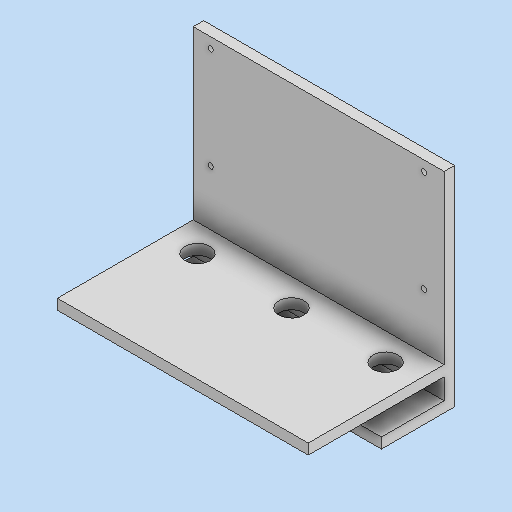
# Autodesk Inventor part: Support_arduino_grand_robot
Saved by Autodesk Inventor 2026 (Build 300175050, 175E)
## iProperties
Created: 2025-06-19
Part Number: Support_arduino_grand_robot
Material: Generisch
Document SubType Name: Modeling
Designer: karle
Density: 1 g/cm^3
Appearance: Vorgabe
Author: karle
Autodesk Inventor part; units mm, degrees
ref_plane "YZ Plane" through (0, 0, 0) normal (1, 0, 0) x (0, 1, 0)
ref_plane "XZ Plane" through (0, 0, 0) normal (0, 1, 0) x (-1, 0, 0)
ref_plane "XY Plane" through (0, 0, 0) normal (0, 0, 1) x (1, 0, 0)
sketch "Skizze1" plane through (0, 0, 0) normal (0, 0, 1) x (1, 0, 0)
  line L0 (-60, 0) -> (60, 0)
  line L1 (60, 0) -> (60, -100)
  line L2 (60, -100) -> (-60, -100)
  line L3 (-60, -100) -> (-60, 0)
  line L4 (0, 23.1579) -> (0, -78.4962)
  point P0 (0, 0)
  point P1 (0, 0)
  dimension "d0" = 120
  dimension "d1" = 100
  dimension "d2" = 0
  constraints: 10 end point, 2 parallel, 1 coincident, 1 horizontal, 1 midpoint, 1 perpendicular, 1 vertical, 1 other
  measures "d0" distance of L1.end L2.end
  measures "d1" distance between parallel lines of L2 L0
  measures "d2" distance from line of point (0, 0) L0
extrude "Extrusion1" add sketch "Skizze1" against normal blind 5
sketch "Skizze2" plane through (0, 0, 0) normal (0, 0, 1) x (1, 0, 0)
  line L0 (-60, -100) -> (-60, 0) projected
  line L1 (60, -100) -> (-60, -100) projected
  line L2 (-60, -95) -> (60, -95)
  line L3 (60, -95) -> (60, -100)
  line L4 (60, -100) -> (-60, -100)
  line L5 (-60, -100) -> (-60, -95)
  line L6 (-60, -80) -> (60, -80)
  line L7 (60, -80) -> (60, -85)
  line L8 (60, -85) -> (-60, -85)
  line L9 (-60, -85) -> (-60, -80)
  point P0 (0, 0)
  point P1 (-60, -85)
  dimension "d5" = 5
  dimension "d6" = 5
  dimension "d7" = 15
  constraints: 16 end point, 4 parallel, 3 point on line, 2 horizontal, 2 perpendicular
  measures "d5" distance between parallel lines of L1 L2
  measures "d6" distance between parallel lines of L8 L6
  measures "d7" distance between parallel lines of L1 L8
extrude "Extrusion2" add sketch "Skizze2" along normal blind 30 contours L0 L2 L3 L1
extrude "Extrusion3" add sketch "Skizze2" along normal blind 65 contours L0 L6 L7 L8
sketch "Skizze3" plane through (0, 0, 0) normal (0, 0, 1) x (1, 0, 0)
  line L0 (0, 0) -> (0, -100.1543)
  line L1 (60, 0) -> (-60, 0) projected
  point P0 (-51.627, -5)
  point P1 (50.373, -5)
  point P2 (50.373, -53.5)
  point P3 (-51.627, -53.5)
  dimension "d12" = 102
  dimension "d13" = 48.5
  dimension "d14" = 5
  constraints: 2 end point, 1 horizontal alignment, 1 vertical
  measures "d12" distance of point (50.373, -5) point (-51.627, -5)
  measures "d13" distance of point (50.373, -53.5) point (50.373, -5)
  measures "d14" distance from line of point (50.373, -5) L1
hole "Bohrung1" at (50.373, -5, 0) at (50.373, -53.5, 0) at (-51.627, -53.5, 0) at (-51.627, -5, 0) direction (0, 0, -1) diameter 2.5 end through all clearance for "Flachkopfmaschinenschraube" size "M2" standard "ANSI Metrisches M Profil"
sketch "Skizze5" plane through (-60, -100, -5) normal (0, -1, 0) x (1, 0, 0)
  line L0 (60, 91.0328) -> (60, -23.9395)
  line L1 (0, 35) -> (0, 0) projected
  point P0 (60, 5)
  point P1 (105, 18.1412)
  point P2 (15, 18.1412)
  point P3 (60, 18.1412)
  dimension "d27" = 90
  dimension "d28" = 60
  constraints: 2 end point, 2 horizontal alignment, 1 point on line, 1 symmetric about line, 1 vertical
  measures "d27" distance of point (15, 18.141) point (105, 18.141)
  measures "d28" distance between parallel lines of L1 L0
hole "Bohrung2" at (45, -100, 13.1412) at (-45, -100, 13.1412) at (0, -100, 13.1412) direction (0, 1, 0) diameter 5.5 end through all
sketch "Skizze6" plane through (-60, -80, 0) normal (0, 1, 0) x (1, 0, 0)
  line L0 (0, 5) -> (120, 5) projected
  line L1 (0, 0) -> (0, -65) projected
  point P0 (60, 0)
  point P1 (105, -13)
  point P2 (60, -13)
  point P3 (15, -13)
  dimension "d36" = 18
  dimension "d37" = 90
  dimension "d38" = 60
  dimension "d39" = 15
  constraints: 2 horizontal alignment
  measures "d36" distance from line of L0 point (15, -13)
  measures "d37" distance of point (105, -13) point (15, -13)
  measures "d38" distance from line of L1 point (60, -13)
  measures "d39" distance from line of L1 point (15, -13)
hole "Bohrung3" at (45, -80, 13) at (0, -80, 13) at (-45, -80, 13) direction (0, -1, 0) diameter 12 depth 15
